Autodesk Fusion 360 part; units mm, degrees
(part 2 of 5)
equation "d84 = plt_border_width_Ref"
equation "d85 = plt_border_width_Ref"
equation "d86 = plt_border_width_Ref"
equation "d87 = plt_border_width_Ref"
equation "d88 = plt_border_width_Ref"
equation "d89 = plt_border_width_Ref"
equation "d90 = plt_border_width_Ref"
equation "d91 = plt_border_width_Ref"
equation "d92 = plt_border_width_Ref"
equation "d93 = plt_border_width_Ref"
equation "d94 = plt_border_width_Ref"
equation "d95 = plt_border_width_Ref"
equation "d96 = plt_border_width_Ref"
equation "d97 = plt_border_width_Ref"
equation "d98 = plt_border_width_Ref"
equation "d99 = plt_border_width_Ref"
equation "d100 = plt_border_width_Ref"
equation "d101 = plt_border_width_Ref"
equation "d102 = plt_border_width_Ref"
equation "d103 = -case_border_width_Ref"
equation "d104 = plt_border_width_Ref"
equation "d105 = -case_bot_max_thickness_Ref"
equation "d107 = case_border_width_Ref"
equation "d108 = case_border_width_Ref"
equation "d109 = case_border_width_Ref"
equation "d110 = case_border_width_Ref"
equation "d112 = case_border_width_Ref"
equation "d113 = case_border_width_Ref"
equation "d114 = case_border_width_Ref * 1.75"
equation "d115 = case_border_width_Ref"
equation "d116 = case_border_width_Ref"
equation "d117 = case_border_width_Ref * 1.75"
equation "d118 = case_border_width_Ref"
equation "d119 = case_border_width_Ref"
equation "d120 = case_border_width_Ref * 1.75"
equation "d121 = case_border_width_Ref"
equation "d122 = case_border_width_Ref"
equation "d123 = case_border_width_Ref * 1.75"
equation "d124 = m2scr_diameter_Ref"
equation "d125 = assemblyscr_head_diameter_Ref"
equation "d126 = assemblyscr_head_diameter_Ref"
equation "d127 = m2scr_diameter_Ref"
equation "d128 = assemblyscr_head_diameter_Ref"
equation "d129 = m2scr_diameter_Ref"
equation "d130 = assemblyscr_head_diameter_Ref"
equation "d131 = m2scr_diameter_Ref"
equation "d134 = plt_border_width_Ref + sw_size_Ref"
equation "d135 = plt_border_width_Ref + sw_size_Ref + 0.375 mm"
equation "d138 = plt_border_width_Ref + sw_size_Ref"
equation "d139 = plt_border_width_Ref + sw_size_Ref - 0.375 mm"
equation "d140 = plt_border_width_Ref + sw_size_Ref"
equation "d141 = plt_border_width_Ref + sw_size_Ref"
equation "d142 = sw_size_Ref * 3 - 0.55 mm"
equation "d146 = plt_border_width_Ref + sw_size_Ref * 3 - col_pinky_offset_Ref"
equation "d147 = sw_size_Ref * 6 + plt_border_width_Ref"
equation "d148 = plt_border_width_Ref + 13.096875 mm"
equation "d150 = sw_size_Ref * 2 + 8.334375 mm"
equation "d151 = 3.571875 mm + plt_border_width_Ref"
equation "d152 = m2scr_diameter_Ref"
equation "d153 = mtscr_head_diameter_Ref"
equation "d154 = m2scr_diameter_Ref"
equation "d155 = mtscr_head_diameter_Ref"
equation "d156 = m2scr_diameter_Ref"
equation "d157 = mtscr_head_diameter_Ref"
equation "d158 = m2scr_diameter_Ref"
equation "d159 = mtscr_head_diameter_Ref"
equation "d160 = m2scr_diameter_Ref"
equation "d161 = mtscr_head_diameter_Ref"
equation "d162 = m2scr_diameter_Ref"
equation "d163 = mtscr_head_diameter_Ref"
equation "d165 = case_border_width_Ref + plt_border_width_Ref"
equation "d166 = case_border_width_Ref + plt_border_width_Ref"
equation "d167 = sw_size_Ref * 3"
equation "d168 = plt_border_width_Ref + case_border_width_Ref"
equation "d169 = case_border_width_Ref"
equation "d170 = alignh_diameter_Ref"
equation "d171 = case_border_width_Ref + plt_border_width_Ref"
equation "d172 = alignh_diameter_Ref"
equation "d173 = case_border_width_Ref + plt_border_width_Ref"
equation "d174 = alignh_diameter_Ref"
equation "d175 = case_border_width_Ref + plt_border_width_Ref"
equation "d177 = plt_border_width_Ref + sw_size_Ref * 3"
equation "d178 = case_border_width_Ref"
equation "d179 = plt_border_width_Ref"
equation "d180 = case_border_width_Ref + plt_border_width_Ref"
equation "d181 = case_border_width_Ref"
equation "d182 = plt_border_width_Ref"
equation "d184 = sw_size_Ref * 3 + plt_border_width_Ref"
equation "d185 = case_border_width_Ref"
equation "d186 = alignh_diameter_Ref"
equation "d187 = alignh_diameter_Ref"
equation "d188 = alignh_height_Ref"
equation "d191 = ( alignh_diameter_Ref ) * 0.5"
equation "d192 = -case_bot_max_thickness_Ref + 0.5 mm"
equation "d194 = -case_bot_max_thickness_Ref + min(1 mm; case_bot_min_thickness_Ref - mtscr_head_width_Ref)"
equation "d196 = case_border_width_Ref + plt_border_width_Ref"
equation "d197 = case_border_width_Ref + plt_border_width_Ref"
equation "d198 = bat_offset_Ref - bat_length_Ref * 0.5 - bat_wall_thickness_Ref"
equation "d199 = bat_height_Ref + bat_wall_thickness_Ref * 2"
equation "d200 = bat_length_Ref + bat_wall_thickness_Ref * 2"
equation "d201 = bat_wall_thickness_Ref"
equation "d202 = bat_wall_thickness_Ref"
equation "d203 = bat_wall_thickness_Ref"
equation "d204 = ( pcb_clearance_Ref ) - ( sw_hotswap_clearance_Ref + bat_width_Ref + bat_wall_thickness_Ref + 0.05 mm )"
equation "d206 = ( bat_height_Ref + bat_wall_thickness_Ref * 2 ) * 0.5"
equation "d207 = bat_wall_thickness_Ref * 0.5"
equation "d208 = bat_wall_thickness_Ref"
equation "d209 = bat_wall_thickness_Ref"
equation "d210 = bat_length_Ref"
equation "d212 = bat_wall_thickness_Ref"
equation "d214 = ( bat_width_Ref + bat_wall_thickness_Ref ) * 0.5"
equation "d218 = bat_wall_thickness_Ref * 0.5"
equation "d219 = bat_wall_thickness_Ref"
equation "d220 = bat_length_Ref"
equation "d221 = bat_width_Ref + bat_wall_thickness_Ref"
equation "d225 = -case_bot_angle_Ref"
equation "d229 = rf_voffset_Ref"
equation "d230 = rf_hoffset_Ref"
equation "d231 = rf_voffset_Ref"
equation "d232 = rf_hoffset_Ref"
equation "d233 = rf_voffset_Ref"
equation "d234 = rf_hoffset_Ref"
equation "d235 = rf_voffset_Ref"
equation "d236 = rf_hoffset_Ref"
equation "d237 = rf_diameter_Ref"
equation "d238 = rf_diameter_Ref"
equation "d239 = rf_diameter_Ref"
equation "d240 = rf_diameter_Ref"
equation "d243 = -rf_width_Ref"
equation "d246 = case_side_fillet_Ref"
equation "case_side_fillet_Ref = 2.5 mm"
equation "case_top_fillet_Ref = 0.5 mm"
equation "case_top_inner_border_side_fillet_Ref = 1.5 mm"
equation "case_top_inner_border_top_fillet_Ref = 1 mm"
equation "usbc_contour_height_Ref = 4.5 mm"
equation "usbc_contour_length_Ref = 12 mm"
equation "assemblyscr_head_diameter_Ref = 4.15 mm"
equation "assemblyscr_head_width_Ref = 0.85 mm"
equation "rf_diameter_Ref = 10 mm"
equation "rf_width_Ref = 0.5 mm"
equation "rf_voffset_Ref = case_border_width_Ref + 10 mm"
equation "rf_hoffset_Ref = case_border_width_Ref + 15 mm"

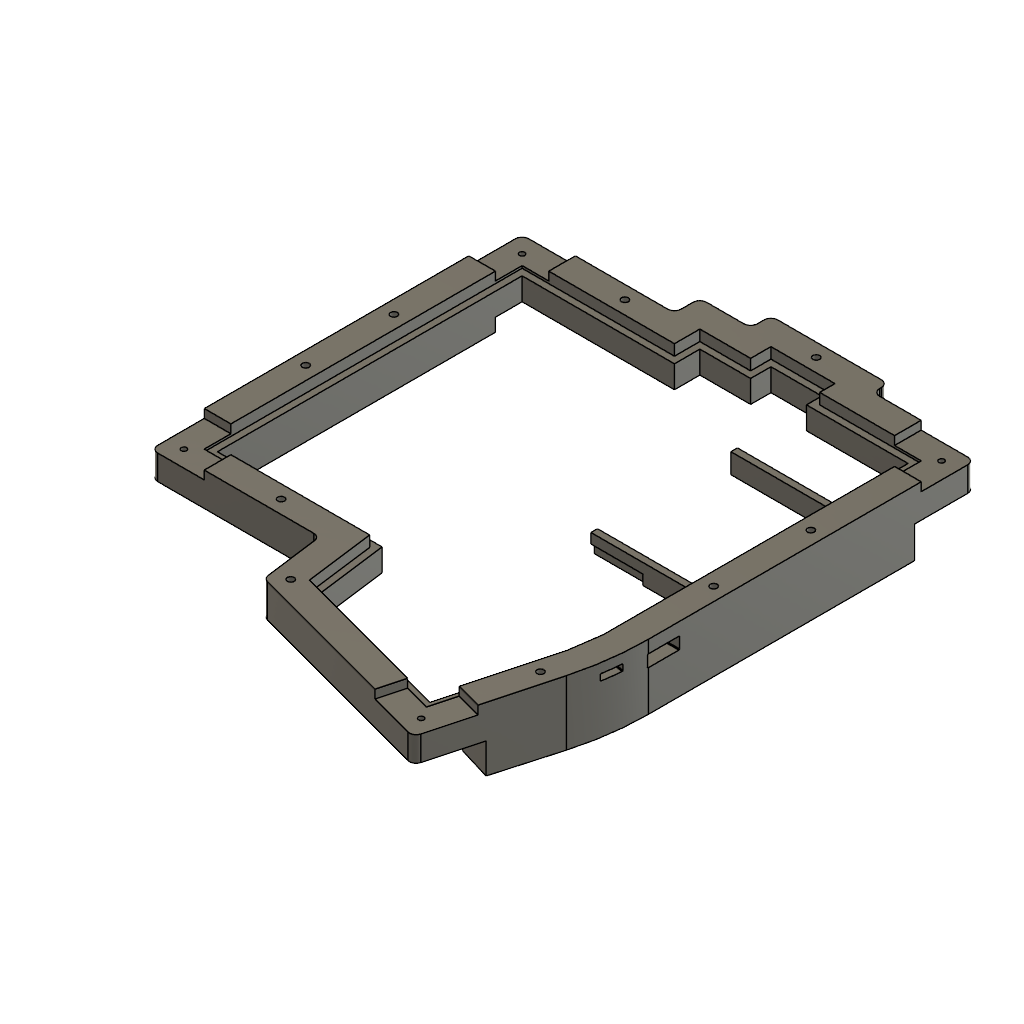
design "Case Wall (Castor)" references "_Globals"
part number: 2026-10-18-13-23-20-867
Autodesk Fusion 360 part; units mm, degrees
derive "ExternalDerived1"
sketch "Sketch1" plane through (0, 0, 0) normal (0, 1, 0) x (1, 0, 0)
  line L0 (-9.525, 57.15) -> (-66.675, 57.15) construction
  line L1 (-66.675, 57.15) -> (-66.675, -57.15) construction
  line L2 (-66.675, -57.15) -> (-9.525, -57.15) construction
  line L3 (66.675, -45.72) -> (66.675, 57.15) construction
  line L4 (66.675, 57.15) -> (-66.675, -57.15) construction
  line L5 (-66.675, 57.15) -> (66.675, -57.15) construction
  line L6 (-66.675, 57.15) -> (-9.525, 57.15) construction
  line L7 (-9.525, 57.15) -> (-9.525, 66.675) construction
  line L8 (-9.525, 66.675) -> (9.525, 66.675) construction
  line L9 (9.525, 66.675) -> (9.525, 74.295) construction
  line L10 (9.525, 74.295) -> (28.575, 74.295) construction
  line L11 (28.575, 74.295) -> (28.575, 68.58) construction
  line L12 (28.575, 68.58) -> (66.675, 68.58) construction
  line L13 (66.675, 68.58) -> (66.675, 57.15) construction
  line L14 (-66.675, -57.15) -> (-9.525, -57.15) construction
  line L15 (-9.525, -57.15) -> (-9.525, -47.625) construction
  line L16 (-9.525, -47.625) -> (9.525, -47.625) construction
  line L17 (9.525, -47.625) -> (9.525, -45.72) construction
  line L18 (9.525, -45.72) -> (66.675, -45.72) construction
  line L19 (9.525, -47.625) -> (9.525, -47.73) construction
  line L20 (9.525, -47.73) -> (9.59, -47.73) construction
  line L21 (9.59, -47.73) -> (9.7259, -47.2229) construction
  line L22 (9.7259, -47.2229) -> (9.2188, -47.087) construction
  line L23 (9.2188, -47.087) -> (27.6197, -52.0175) construction
  line L24 (27.6197, -52.0175) -> (22.6892, -70.4184) construction
  line L25 (22.6892, -70.4184) -> (4.2883, -65.4879) construction
  line L26 (4.2883, -65.4879) -> (9.2188, -47.087) construction
  line L27 (27.6197, -52.0175) -> (64.4214, -61.8785) construction
  line L28 (64.4214, -61.8785) -> (54.5604, -98.6803) construction
  line L29 (54.5604, -98.6803) -> (-0.6422, -83.8888) construction
  line L30 (-0.6422, -83.8888) -> (4.2883, -65.4879) construction
  line L31 (-66.675, -57.15) -> (-69.15, -57.15) construction
  line L32 (-69.15, -57.15) -> (-69.15, -59.625) construction
  line L33 (-9.525, -57.15) -> (-7.05, -57.15) construction
  line L34 (-7.05, -57.15) -> (-7.05, -59.625) construction
  line L35 (-0.6422, -83.8888) -> (-3.0329, -83.2482) construction
  line L36 (-3.0329, -83.2482) -> (-3.6735, -85.6389) construction
  line L37 (54.5604, -98.6803) -> (56.9511, -99.3209) construction
  line L38 (56.9511, -99.3209) -> (56.3105, -101.7115) construction
  line L39 (64.4214, -61.8785) -> (65.062, -59.4879) construction
  line L40 (65.062, -59.4879) -> (67.4527, -60.1284) construction
  line L41 (66.675, -45.72) -> (66.675, -48.195) construction
  line L42 (66.675, -48.195) -> (69.15, -48.195) construction
  line L43 (66.675, 68.58) -> (66.675, 71.055) construction
  line L44 (66.675, 71.055) -> (69.15, 71.055) construction
  line L45 (28.575, 68.58) -> (31.05, 68.58) construction
  line L46 (31.05, 68.58) -> (31.05, 71.055) construction
  line L47 (28.575, 74.295) -> (28.575, 76.77) construction
  line L48 (28.575, 76.77) -> (31.05, 76.77) construction
  line L49 (9.525, 74.295) -> (9.525, 76.77) construction
  line L50 (9.525, 76.77) -> (7.05, 76.77) construction
  line L51 (9.525, 66.675) -> (7.05, 66.675) construction
  line L52 (7.05, 66.675) -> (7.05, 69.15) construction
  line L53 (-9.525, 66.675) -> (-12, 66.675) construction
  line L54 (-12, 66.675) -> (-12, 69.15) construction
  line L55 (-9.525, 57.15) -> (-12, 57.15) construction
  line L56 (-12, 57.15) -> (-12, 59.625) construction
  line L57 (-66.675, 57.15) -> (-69.15, 57.15) construction
  line L58 (-69.15, 57.15) -> (-69.15, 59.625) construction
  line L59 (-69.15, -59.625) -> (-69.15, 59.625)
  line L60 (-69.15, 59.625) -> (-12, 59.625)
  line L61 (-12, 69.15) -> (-12, 59.625)
  line L62 (-12, 69.15) -> (7.05, 69.15)
  line L63 (7.05, 69.15) -> (7.05, 76.77)
  line L64 (7.05, 76.77) -> (31.05, 76.77)
  line L65 (31.05, 76.77) -> (31.05, 71.055)
  line L66 (31.05, 71.055) -> (69.15, 71.055)
  line L67 (69.15, 71.055) -> (69.15, -48.195)
  line L68 (69.15, -48.195) -> (67.4527, -60.1284)
  line L69 (67.4527, -60.1284) -> (56.3105, -101.7115)
  line L70 (56.3105, -101.7115) -> (-3.6735, -85.6389)
  line L71 (-3.6735, -85.6389) -> (-7.05, -59.625)
  line L72 (-7.05, -59.625) -> (-69.15, -59.625)
  line L73 (-22, 79.15) -> (-22, 69.625)
  line L74 (-79.15, 69.625) -> (-22, 69.625)
  line L75 (-79.15, -69.625) -> (-79.15, 69.625)
  line L76 (-15.8359, -69.625) -> (-79.15, -69.625)
  line L77 (-12.7285, -93.5653) -> (-15.8359, -69.625)
  line L78 (63.3816, -113.959) -> (-12.7285, -93.5653)
  line L79 (77.2681, -62.1339) -> (63.3816, -113.959)
  line L80 (79.15, -48.9026) -> (77.2681, -62.1339)
  line L81 (79.15, 81.055) -> (79.15, -48.9026)
  line L82 (41.05, 81.055) -> (79.15, 81.055)
  line L83 (41.05, 86.77) -> (41.05, 81.055)
  line L84 (-2.95, 86.77) -> (41.05, 86.77)
  line L85 (-2.95, 79.15) -> (-2.95, 86.77)
  line L86 (-22, 79.15) -> (-2.95, 79.15)
  dimension "d44" = 133.35
  dimension "d45" = 114.3
  dimension "d46" = 57.15
  dimension "d47" = 9.525
  dimension "d48" = 19.05
  dimension "d49" = 7.62
  dimension "d50" = 19.05
  dimension "d51" = 5.715
  dimension "d52" = 38.1
  dimension "d53" = 57.15
  dimension "d54" = 9.525
  dimension "d55" = 19.05
  dimension "d56" = 1.905
  dimension "d57" = 102.87
  dimension "d58" = 0.105
  dimension "d59" = 0.065
  dimension "d60" = 0.525
  dimension "d61" = 0.525
  dimension "d62" = 19.05
  dimension "d63" = 19.05
  dimension "d64" = 38.1
  dimension "d65" = 38.1
  dimension "d66" = 57.15
  dimension "d67" = 2.475
  dimension "d68" = 2.475
  dimension "d69" = 2.475
  dimension "d70" = 2.475
  dimension "d71" = 2.475
  dimension "d72" = 2.475
  dimension "d73" = 2.475
  dimension "d74" = 2.475
  dimension "d75" = 2.475
  dimension "d76" = 2.475
  dimension "d77" = 2.475
  dimension "d78" = 2.475
  dimension "d79" = 2.475
  dimension "d80" = 2.475
  dimension "d81" = 2.475
  dimension "d82" = 2.475
  dimension "d83" = 2.475
  dimension "d84" = 2.475
  dimension "d85" = 2.475
  dimension "d86" = 2.475
  dimension "d87" = 2.475
  dimension "d88" = 2.475
  dimension "d89" = 2.475
  dimension "d90" = 2.475
  dimension "d91" = 2.475
  dimension "d92" = 2.475
  dimension "d93" = 2.475
  dimension "d94" = 2.475
  constraint horizontal L0
  constraint perpendicular L0 L1
  constraint parallel L0 L2
  constraint parallel L1 L3
  constraint coincident L4 origin
  constraint coincident L5 origin
  constraint perpendicular L1 L6
  constraint perpendicular L0 L7
  constraint perpendicular L7 L8
  constraint perpendicular L0 L9
  constraint perpendicular L9 L10
  constraint perpendicular L0 L11
  constraint perpendicular L11 L12
  constraint perpendicular L1 L14
  constraint perpendicular L2 L15
  constraint perpendicular L15 L16
  constraint perpendicular L2 L17
  constraint perpendicular L3 L18
  constraint collinear L3 L13
  constraint vertical L19
  constraint perpendicular L19 L20
  constraint perpendicular L21 L22
  constraint parallel L24 L26
  constraint parallel L23 L25
  constraint perpendicular L24 L25
  constraint collinear L22 L23
  constraint perpendicular L24 L27
  constraint perpendicular L27 L28
  constraint perpendicular L28 L29
  constraint perpendicular L1 L31
  constraint perpendicular L14 L32
  constraint perpendicular L15 L33
  constraint perpendicular L2 L34
  constraint perpendicular L30 L35
  constraint perpendicular L29 L36
  constraint perpendicular L28 L37
  constraint perpendicular L29 L38
  constraint perpendicular L27 L39
  constraint perpendicular L39 L40
  constraint perpendicular L18 L41
  constraint perpendicular L3 L42
  constraint perpendicular L12 L43
  constraint perpendicular L13 L44
  constraint perpendicular L11 L45
  constraint perpendicular L12 L46
  constraint perpendicular L10 L47
  constraint perpendicular L47 L48
  constraint perpendicular L10 L49
  constraint perpendicular L9 L50
  constraint perpendicular L9 L51
  constraint perpendicular L51 L52
  constraint perpendicular L7 L53
  constraint perpendicular L8 L54
  constraint perpendicular L7 L55
  constraint perpendicular L6 L56
  constraint perpendicular L1 L57
  constraint perpendicular L57 L58
  measures "d44" distance of L1.end L5.end
  measures "d45" distance of L0.end L1.end
  measures "d46" distance of L0.end L0.start
  measures "d47" distance of L0.start L7.end
  measures "d48" distance of L7.end L8.end
  measures "d49" distance of L8.end L9.end
  measures "d50" distance of L9.end L10.end
  measures "d51" distance of L10.end L11.end
  measures "d52" distance of L11.end L12.end
  measures "d53" distance of L1.end L2.end
  measures "d54" distance of L2.end L15.end
  measures "d55" distance of L15.end L16.end
  measures "d56" distance of L16.end L17.end
  measures "d57" distance of L3.end L3.start
  measures "d58" distance of L16.end L19.end
  measures "d59" distance of L19.end L20.end
  measures "d60" distance of L20.end L21.end
  measures "d61" distance of L21.end L22.end
  measures "d62" distance of L22.end L23.end
  measures "d63" distance of L22.end L25.end
  measures "d64" distance of L23.end L27.end
  measures "d65" distance of L27.end L28.end
  measures "d66" distance of L28.end L29.end
  measures "d67" distance of L1.end L31.end
  measures "d68" distance of L31.end L32.end
  measures "d69" distance of L2.end L33.end
  measures "d70" distance of L33.end L34.end
  measures "d71" distance of L29.end L35.end
  measures "d72" distance of L35.end L36.end
  measures "d73" distance of L28.end L37.end
  measures "d74" distance of L37.end L38.end
  measures "d75" distance of L27.end L39.end
  measures "d76" distance of L39.end L40.end
  measures "d77" distance of L3.start L41.end
  measures "d78" distance of L41.end L42.end
  measures "d79" distance of L12.end L43.end
  measures "d80" distance of L43.end L44.end
  measures "d81" distance of L11.end L45.end
  measures "d82" distance of L45.end L46.end
  measures "d83" distance of L10.end L47.end
  measures "d84" distance of L47.end L48.end
  measures "d85" distance of L9.end L49.end
  measures "d86" distance of L49.end L50.end
  measures "d87" distance of L8.end L51.end
  measures "d88" distance of L51.end L52.end
  measures "d89" distance of L7.end L53.end
  measures "d90" distance of L53.end L54.end
  measures "d91" distance of L0.start L55.end
  measures "d92" distance of L55.end L56.end
  measures "d93" distance of L0.end L57.end
  measures "d94" distance of L57.end L58.end
extrude "Extrude1" add sketch "Sketch1" along normal blind 24.3975
sketch "Sketch2" plane through (0, 24.3975, 0) normal (0, 1, 0) x (-1, 0, 0)
  line L0 (12, -59.625) -> (12, -69.15)
  line L1 (12, -69.15) -> (-7.05, -69.15)
  line L2 (-7.05, -69.15) -> (-7.05, -76.77)
  line L3 (-7.05, -76.77) -> (-31.05, -76.77)
  line L4 (-31.05, -76.77) -> (-31.05, -71.055)
  line L5 (-31.05, -71.055) -> (-69.15, -71.055)
  line L6 (-69.15, -71.055) -> (-69.15, 48.195)
  line L7 (-69.15, 48.195) -> (-67.4527, 60.1284)
  line L8 (-67.4527, 60.1284) -> (-56.3105, 101.7115)
  line L9 (-56.3105, 101.7115) -> (3.6735, 85.6389)
  line L10 (3.6735, 85.6389) -> (7.05, 59.625)
  line L11 (7.05, 59.625) -> (69.15, 59.625)
  line L12 (69.15, 59.625) -> (69.15, -59.625)
  line L13 (69.15, -59.625) -> (12, -59.625)
  line L14 (22, -79.15) -> (22, -69.625)
  line L15 (22, -69.625) -> (79.15, -69.625)
  line L16 (79.15, -69.625) -> (79.15, 69.625)
  line L17 (79.15, 69.625) -> (15.8359, 69.625)
  line L18 (15.8359, 69.625) -> (12.7285, 93.5653)
  line L19 (12.7285, 93.5653) -> (-63.3816, 113.959)
  line L20 (-63.3816, 113.959) -> (-77.2681, 62.1339)
  line L21 (-77.2681, 62.1339) -> (-79.15, 48.9026)
  line L22 (-79.15, 48.9026) -> (-79.15, -81.055)
  line L23 (-79.15, -81.055) -> (-41.05, -81.055)
  line L24 (-41.05, -81.055) -> (-41.05, -86.77)
  line L25 (-41.05, -86.77) -> (2.95, -86.77)
  line L26 (2.95, -86.77) -> (2.95, -79.15)
  line L27 (2.95, -79.15) -> (22, -79.15)
  line L28 (69.15, -59.625) -> (59.15, -59.625)
  line L29 (59.15, -59.625) -> (59.15, -69.625)
  line L30 (69.15, -59.625) -> (69.15, -49.625)
  line L31 (69.15, -49.625) -> (79.15, -49.625)
  line L32 (-69.15, -71.055) -> (-59.15, -71.055)
  line L33 (-59.15, -71.055) -> (-59.15, -81.055)
  line L34 (-69.15, -71.055) -> (-69.15, -61.055)
  line L35 (-69.15, -61.055) -> (-79.15, -61.055)
  line L36 (69.15, 59.625) -> (59.15, 59.625)
  line L37 (59.15, 59.625) -> (59.15, 69.625)
  line L38 (69.15, 59.625) -> (69.15, 49.625)
  line L39 (69.15, 49.625) -> (79.15, 49.625)
  line L40 (-56.3105, 101.7115) -> (-46.6513, 99.1233)
  line L41 (-46.6513, 99.1233) -> (-44.0631, 108.7826)
  line L42 (-56.3105, 101.7115) -> (-58.8987, 92.0523)
  line L43 (-58.8987, 92.0523) -> (-68.558, 94.6405)
  line L44 (-56.3105, 101.7115) -> (-63.3816, 113.959) construction
  line L45 (69.15, 59.625) -> (79.15, 69.625) construction
  line L46 (69.15, -59.625) -> (79.15, -69.625) construction
  line L47 (-69.15, -71.055) -> (-79.15, -81.055) construction
  circle A0 centre (79.15, -69.625) radius 8.75 construction
  circle A1 centre (-79.15, -81.055) radius 8.75 construction
  circle A2 centre (-63.3816, 113.959) radius 8.75 construction
  circle A3 centre (79.15, 69.625) radius 8.75 construction
  circle A4 centre (72.9628, 63.4378) radius 1.025
  circle A5 centre (-59.0066, 106.3813) radius 1.025
  circle A6 centre (-72.9628, -74.8678) radius 1.025
  circle A7 centre (72.9628, -63.4378) radius 1.025
  line L48 (-19.05, -86.77) -> (-19.05, -76.77) construction
  line L49 (59.15, -59.625) -> (12, -59.625) construction
  line L50 (35.575, -59.625) -> (35.575, -69.625) construction
  circle A8 centre (35.575, -64.625) radius 1.275
  circle A9 centre (-19.05, -81.77) radius 1.275
  line L51 (15.8359, 69.625) -> (7.05, 59.625) construction
  line L52 (3.6735, 85.6389) -> (12.7285, 93.5653) construction
  line L53 (59.15, 64.625) -> (11.443, 64.625) construction
  circle A10 centre (35.2965, 64.625) radius 1.275
  line L54 (-26.3185, 93.6752) -> (-23.7303, 103.3345) construction
  line L55 (14.2822, 81.5952) -> (5.3617, 72.6319) construction
  line L56 (9.822, 77.1136) -> (-25.0244, 98.5048) construction
  line L57 (-7.6012, 87.8092) -> (12.7285, 93.5653) construction
  line L58 (2.5637, 90.6873) -> (8.201, 89.6021) construction
  line L59 (2.5637, 90.6873) -> (6.6059, 88.2058) construction
  line L60 (6.6059, 88.2058) -> (8.201, 89.6021) construction
  circle A11 centre (7.4035, 88.904) radius 1.275
  line L61 (74.15, -49.625) -> (74.15, 49.625) construction
  line L62 (74.15, -49.625) -> (143.9366, 68.7503) construction
  circle A12 centre (74.15, -49.625) radius 30 construction
  circle A13 centre (89.3856, -23.7817) radius 30 construction
  circle A14 centre (104.6212, 2.0616) radius 30 construction
  line L63 (119.8568, 27.9049) -> (74.15, 49.625) construction
  circle A15 centre (119.8568, 27.9049) radius 30 construction
  line L64 (104.6212, 2.0616) -> (92.7606, 40.7812) construction
  circle A16 centre (74.15, -49.625) radius 40.4954 construction
  circle A17 centre (89.3856, -23.7817) radius 40.4954 construction
  line L65 (89.3856, -23.7817) -> (129.6396, -28.1962) construction
  line L66 (74.15, -49.625) -> (114.404, -54.0395) construction
  line L67 (77.525, 14.9378) -> (104.6212, 2.0616) construction
  line L68 (77.525, 14.9378) -> (34.0227, 35.6103) construction
  line L69 (89.3856, -23.7817) -> (62.2894, -10.9055) construction
  circle A18 centre (74.15, 16.5417) radius 1.275
  circle A19 centre (74.15, -16.5417) radius 1.275
  line L70 (-69.15, 48.195) -> (-79.15, 48.195) construction
  line L71 (-74.15, 48.195) -> (-74.15, -61.055) construction
  line L72 (-74.15, -61.055) -> (-143.6538, 60.5776) construction
  circle A20 centre (-74.15, -61.055) radius 30 construction
  circle A21 centre (-89.0341, -35.0077) radius 30 construction
  circle A22 centre (-103.9182, -8.9603) radius 30 construction
  line L73 (-118.8022, 17.087) -> (-74.15, 48.195) construction
  circle A23 centre (-118.8022, 17.087) radius 30 construction
  line L74 (-103.9182, -8.9603) -> (-94.1868, 34.2359) construction
  circle A24 centre (-74.15, -61.055) radius 44.2788 construction
  circle A25 centre (-89.0341, -35.0077) radius 44.2788 construction
  line L75 (-74.15, -61.055) -> (-114.463, -79.371) construction
  line L76 (-89.0341, -35.0077) -> (-129.347, -53.3236) construction
  line L77 (-89.0341, -35.0077) -> (-64.4187, -17.8588) construction
  line L78 (-103.9182, -8.9603) -> (-79.3028, 8.1885) construction
  line L79 (-79.3028, 8.1885) -> (-64.4187, 18.5579) construction
  circle A26 centre (-74.15, 11.7783) radius 1.275
  circle A27 centre (-74.15, -24.6383) radius 1.275
  line L80 (-67.4527, 60.1284) -> (-77.1119, 62.7166) construction
  line L81 (-63.7283, 93.3464) -> (-72.2823, 61.4225) construction
  line L82 (-72.2823, 61.4225) -> (-84.2833, 106.1662) construction
  circle A28 centre (-72.2823, 61.4225) radius 10 construction
  circle A29 centre (-74.8729, 71.0811) radius 10 construction
  circle A30 centre (-77.4635, 80.7398) radius 10 construction
  line L83 (-80.0541, 90.3984) -> (-63.7283, 93.3464) construction
  circle A31 centre (-80.0541, 90.3984) radius 10 construction
  line L84 (-77.4635, 80.7398) -> (-70.2132, 92.1754) construction
  circle A32 centre (-72.2823, 61.4225) radius 13.5403 construction
  line L85 (-72.2823, 61.4225) -> (-58.8852, 63.3864) construction
  line L86 (-65.032, 72.8581) -> (-74.8729, 71.0811) construction
  circle A33 centre (-69.431, 72.0638) radius 1.275
  dimension "d105" = 10
  dimension "d106" = 10
  dimension "d107" = 10
  dimension "d108" = 10
  dimension "d109" = 10
  dimension "d110" = 10
  dimension "d111" = 10
  dimension "d112" = 10
  dimension "d113" = 17.5
  dimension "d114" = 17.5
  dimension "d115" = 17.5
  dimension "d116" = 17.5
  dimension "d117" = 2.05
  dimension "d118" = 2.05
  dimension "d119" = 2.05
  dimension "d120" = 2.05
  dimension "d122" = 2.55
  dimension "d123" = 2.55
  dimension "d124" = 2.55
  dimension "d125" = 2.55
  dimension "d126" = 60
  dimension "d127" = 60
  dimension "d128" = 60
  dimension "d129" = 2.55
  dimension "d130" = 2.55
  dimension "d131" = 60
  dimension "d132" = 60
  dimension "d133" = 60
  dimension "d134" = 2.55
  dimension "d135" = 2.55
  dimension "d195" = 20
  dimension "d196" = 2.55
  constraint coincident L12.end L13.start
  constraint perpendicular L12 L28
  constraint coincident L15 L29.end
  constraint perpendicular L15 L29
  constraint perpendicular L13 L30
  constraint coincident L16 L31.end
  constraint perpendicular L16 L31
  constraint coincident L5.end L6.start
  constraint perpendicular L6 L32
  constraint coincident L23 L33.end
  constraint perpendicular L23 L33
  constraint perpendicular L5 L34
  constraint coincident L22 L35.end
  constraint perpendicular L22 L35
  constraint coincident L11.end L12.start
  constraint perpendicular L12 L36
  constraint coincident L17 L37.end
  constraint perpendicular L17 L37
  constraint perpendicular L11 L38
  constraint coincident L16 L39.end
  constraint perpendicular L16 L39
  constraint coincident L8.end L9.start
  constraint coincident L9 L40.end
  constraint coincident L19 L41.end
  constraint perpendicular L19 L41
  constraint perpendicular L9 L42
  constraint coincident L20 L43.end
  constraint perpendicular L20 L43
  constraint coincident L19.end L20.start
  constraint coincident L16.end L17.start
  constraint coincident L15.end L16.start
  constraint coincident L22.end L23.start
  constraint coincident A3 A4.centre
  constraint coincident L45 A4.centre
  constraint coincident A2 A5.centre
  constraint coincident L44 A5.centre
  constraint coincident A1 A6.centre
  constraint coincident L47 A6.centre
  constraint coincident A0 A7.centre
  constraint coincident L46 A7.centre
  constraint midpoint L25 L48.start
  constraint midpoint L3 L48.end
  constraint coincident L0.start L13.end
  constraint midpoint L49 L50.start
  constraint coincident L15 L50.end
  constraint perpendicular L15 L50
  constraint midpoint L50 A8.centre
  constraint midpoint L48 A9.centre
  constraint coincident L17.end L18.start
  constraint coincident L10.end L11.start
  constraint coincident L9.end L10.start
  constraint coincident L18.end L19.start
  constraint midpoint L37 L53.start
  constraint midpoint L51 L53.end
  constraint midpoint L53 A10.centre
  constraint midpoint L9 L54.start
  constraint coincident L19 L54.end
  constraint perpendicular L19 L54
  constraint midpoint L18 L55.start
  constraint midpoint L10 L55.end
  constraint midpoint L55 L56.start
  constraint midpoint L54 L56.end
  constraint midpoint L56 L57.start
  constraint midpoint L57 L58.start
  constraint midpoint L52 L58.end
  constraint coincident L52 L59.end
  constraint parallel L56 L59
  constraint midpoint L60 A11.centre
  constraint midpoint L31 L61.start
  constraint midpoint L39 L61.end
  constraint coincident L61.start L62.start
  constraint coincident A12 A13.centre
  constraint coincident L62 A13.centre
  constraint coincident A13 A14.centre
  constraint coincident L62 A14.centre
  constraint coincident A14 L63.start
  constraint coincident L62 L63.start
  constraint coincident L63.start A15.centre
  constraint coincident A14.centre A15
  constraint coincident A14.centre L64.start
  constraint coincident A15 L64.end
  constraint coincident L63 L64.end
  constraint concentric A13 A17
  constraint coincident A13.centre A17.centre
  constraint coincident A17 L65.end
  constraint coincident A16 L66.end
  constraint parallel L65 L66
  constraint equal L64 L66
  constraint equal L64 L65
  constraint coincident A14 L67.start
  constraint coincident A17 L67.start
  constraint perpendicular A14 L68
  constraint coincident A16 L69.end
  constraint coincident A13 L69.end
  constraint coincident L68 A18.centre
  constraint coincident L61 A18.centre
  constraint coincident L69 A19.centre
  constraint coincident L61 A19.centre
  constraint coincident L6.end L7.start
  constraint coincident L22 L70.end
  constraint perpendicular L22 L70
  constraint midpoint L70 L71.start
  constraint midpoint L35 L71.end
  constraint coincident L71.end L72.start
  constraint coincident A20 A21.centre
  constraint coincident L72 A21.centre
  constraint coincident A21 A22.centre
  constraint coincident L72 A22.centre
  constraint coincident A22 L73.start
  constraint coincident L72 L73.start
  constraint coincident L73.start A23.centre
  constraint coincident A22.centre A23
  constraint coincident A22.centre L74.start
  constraint coincident A23 L74.end
  constraint coincident L73 L74.end
  constraint concentric A21 A25
  constraint coincident A24 L75.end
  constraint coincident A21.centre A25.centre
  constraint coincident A25 L76.end
  constraint parallel L75 L76
  constraint equal L74 L76
  constraint equal L74 L75
  constraint coincident A24 L77.end
  constraint coincident A21 L77.end
  constraint coincident A22 L78.end
  constraint coincident A25 L78.end
  constraint parallel L78 L79
  constraint coincident L79 A26.centre
  constraint coincident L71 A26.centre
  constraint coincident L77 A27.centre
  constraint coincident L71 A27.centre
  constraint coincident L7.end L8.start
  constraint coincident L20 L80.end
  constraint perpendicular L20 L80
  constraint midpoint L43 L81.start
  constraint midpoint L80 L81.end
  constraint coincident L81.end L82.start
  constraint coincident A28 A29.centre
  constraint coincident L82 A29.centre
  constraint coincident L81.end A29
  constraint coincident A29 A30.centre
  constraint coincident L82 A30.centre
  constraint coincident A29.centre A30
  constraint coincident L82 L83.start
  constraint coincident A30 L83.start
  constraint coincident L83.start A31.centre
  constraint coincident A30.centre A31
  constraint coincident A30.centre L84.start
  constraint coincident A31 L84.end
  constraint coincident L83 L84.end
  constraint concentric A28 A32
  constraint coincident A32 L85.end
  constraint equal L84 L85
  constraint coincident A32 L86.start
  constraint coincident A29 L86.start
  constraint coincident A29.centre L86.end
  constraint coincident L86 A33.centre
  constraint coincident L81 A33.centre
  measures "d105" distance of L12.end L28.end
  measures "d106" distance of L12.end L30.end
  measures "d107" distance of L5.end L32.end
  measures "d108" distance of L5.end L34.end
  measures "d109" distance of L11.end L36.end
  measures "d110" distance of L11.end L38.end
  measures "d111" distance of L8.end L40.end
  measures "d112" distance of L8.end L42.end
  measures "d113" diameter of A0
  measures "d114" diameter of A1
  measures "d115" diameter of A2
  measures "d116" diameter of A3
  measures "d117" diameter of A4
  measures "d118" diameter of A5
  measures "d119" diameter of A6
  measures "d120" diameter of A7
  measures "d122" diameter of A8
  measures "d123" diameter of A9
  measures "d124" diameter of A10
  measures "d125" diameter of A11
  measures "d126" diameter of A12
  measures "d127" diameter of A13
  measures "d128" diameter of A14
  measures "d129" diameter of A18
  measures "d130" diameter of A19
  measures "d131" diameter of A20
  measures "d132" diameter of A21
  measures "d133" diameter of A22
  measures "d134" diameter of A26
  measures "d135" diameter of A27
  measures "d195" diameter of A28
  measures "d196" diameter of A33
extrude "Extrude2" cut sketch "Sketch2" against normal blind 4.95 contours A8 | A9 | A10 | A11 | A18 | A19 | A26 | A27 | A33
fillet "Fillet1" radius 1.275 9 edges at (-34.1078, 19.4475, 65.0861) (-6.2147, 19.4475, 89.365) (75.3387, 19.4475, 12.2394) (75.3387, 19.4475, -24.1773) (20.2387, 19.4475, -81.3089) (-34.3863, 19.4475, -64.1639) (-72.9613, 19.4475, 17.0027) (-72.9613, 19.4475, -16.0806) (70.6197, 19.4475, 72.5249)
extrude "Extrude3" cut sketch "Sketch2" against normal through all contours A4 | A5 | A6 | A7
sketch "Sketch3" plane through (0, 24.3975, 0) normal (0, 1, 0) x (-1, 0, 0)
  circle A0 centre (35.575, -64.625) radius 1.275
  circle A1 centre (7.4035, 88.904) radius 1.275
  circle A2 centre (-19.05, -81.77) radius 1.275
  circle A3 centre (74.15, -16.5417) radius 1.275
  circle A4 centre (-74.15, 11.7783) radius 1.275
  circle A5 centre (35.2965, 64.625) radius 1.275
  circle A6 centre (-74.15, -24.6383) radius 1.275
  circle A7 centre (74.15, 16.5417) radius 1.275
  line L0 (12, -59.625) -> (12, -69.15)
  line L1 (12, -69.15) -> (-7.05, -69.15)
  line L2 (-7.05, -69.15) -> (-7.05, -76.77)
  line L3 (-7.05, -76.77) -> (-31.05, -76.77)
  line L4 (-31.05, -76.77) -> (-31.05, -71.055)
  line L5 (-31.05, -71.055) -> (-69.15, -71.055)
  line L6 (-69.15, -71.055) -> (-69.15, 48.195)
  line L7 (-69.15, 48.195) -> (-67.4527, 60.1284)
  line L8 (-67.4527, 60.1284) -> (-56.3105, 101.7115)
  line L9 (-56.3105, 101.7115) -> (3.6735, 85.6389)
  line L10 (3.6735, 85.6389) -> (7.05, 59.625)
  line L11 (7.05, 59.625) -> (69.15, 59.625)
  line L12 (69.15, 59.625) -> (69.15, -59.625)
  line L13 (69.15, -59.625) -> (12, -59.625)
  line L14 (22, -79.15) -> (22, -69.625)
  line L15 (22, -69.625) -> (79.15, -69.625)
  line L16 (79.15, -69.625) -> (79.15, 69.625)
  line L17 (79.15, 69.625) -> (15.8359, 69.625)
  line L18 (15.8359, 69.625) -> (12.7285, 93.5653)
  line L19 (12.7285, 93.5653) -> (-63.3816, 113.959)
  line L20 (-63.3816, 113.959) -> (-77.2681, 62.1339)
  line L21 (-77.2681, 62.1339) -> (-79.15, 48.9026)
  line L22 (-79.15, 48.9026) -> (-79.15, -81.055)
  line L23 (-79.15, -81.055) -> (-41.05, -81.055)
  line L24 (-41.05, -81.055) -> (-41.05, -86.77)
  line L25 (-41.05, -86.77) -> (2.95, -86.77)
  line L26 (2.95, -86.77) -> (2.95, -79.15)
  line L27 (2.95, -79.15) -> (22, -79.15)
  circle A8 centre (72.9628, -63.4378) radius 1.025
  circle A9 centre (72.9628, 63.4378) radius 1.025
  circle A10 centre (-72.9628, -74.8678) radius 1.025
  circle A11 centre (-59.0066, 106.3813) radius 1.025
  line L28 (9.525, -57.15) -> (9.525, -66.675)
  line L29 (9.525, -66.675) -> (-9.525, -66.675)
  line L30 (-9.525, -66.675) -> (-9.525, -74.295)
  line L31 (-9.525, -74.295) -> (-28.575, -74.295)
  line L32 (-28.575, -74.295) -> (-28.575, -68.58)
  line L33 (-28.575, -68.58) -> (-66.675, -68.58)
  line L34 (-66.675, -68.58) -> (-66.675, 48.0199)
  line L35 (-66.675, 48.0199) -> (-65.0234, 59.6321)
  line L36 (-65.0234, 59.6321) -> (-54.5604, 98.6803)
  line L37 (-54.5604, 98.6803) -> (1.4324, 83.6771)
  line L38 (1.4324, 83.6771) -> (4.8755, 57.15)
  line L39 (4.8755, 57.15) -> (66.675, 57.15)
  line L40 (66.675, 57.15) -> (66.675, -57.15)
  line L41 (66.675, -57.15) -> (9.525, -57.15)
  circle A12 centre (-69.431, 72.0638) radius 1.275
  dimension "d141" = 2.475
extrude "Extrude6" cut sketch "Sketch2" against normal blind 3.2 contours L12 L13 L15 L16 L28 L29 L30 L31 | L11 L12 L16 L17 L36 L37 L38 L39 | L5 L6 L22 L23 L32 L33 L34 L35 | L8 L9 L19 L20 L40 L41 L42 L43
extrude "Extrude4" add sketch "Sketch3" against normal blind 4.05 contours L0 L1 L2 L3 L4 L5 L6 L7 L8 L9 L10 L11 L12 L13
extrude "Extrude7" add 1 faces at (68.325, 20.3475, -30.48) along direction (0, -1, 0) blind 20.3475
extrude "Extrude8" cut sketch "Sketch3" against normal blind 4.05 contours L0 L1 L2 L3 L4 L5 L6 L7 L8 L9 L10 L11 L12 L13
sketch "Sketch4" plane through (66.675, 0, 0) normal (-1, 0, 0) x (0, 0, 1)
  line L0 (48.0199, 20.3475) -> (-68.58, 20.3475)
  line L1 (-68.58, 20.3475) -> (-68.58, 0)
  line L2 (-68.58, 0) -> (48.0199, 0)
  line L3 (48.0199, 0) -> (48.0199, 20.3475)
  line L4 (-68.58, 20.3475) -> (35.61, 20.3475) construction
  line L5 (35.61, 20.3475) -> (35.61, 16.1565) construction
  line L6 (31.44, 18.7165) -> (39.78, 18.7165) construction
  line L7 (39.78, 18.7165) -> (39.78, 16.1565) construction
  line L8 (39.78, 16.1565) -> (31.44, 16.1565) construction
  line L9 (31.44, 16.1565) -> (31.44, 18.7165) construction
  line L10 (31.44, 18.7165) -> (39.78, 16.1565) construction
  line L11 (39.78, 18.7165) -> (31.44, 16.1565) construction
  line L12 (41.61, 19.6865) -> (29.61, 19.6865)
  line L13 (29.61, 19.6865) -> (29.61, 15.1865)
  line L14 (29.61, 15.1865) -> (41.61, 15.1865)
  line L15 (41.61, 15.1865) -> (41.61, 19.6865)
  line L16 (41.61, 19.6865) -> (29.61, 15.1865) construction
  line L17 (29.61, 19.6865) -> (41.61, 15.1865) construction
  line L18 (-68.58, 20.3475) -> (-16.08, 20.3475) construction
  line L19 (-16.08, 20.3475) -> (-16.08, 18.4475) construction
  line L20 (-16.08, 18.4475) -> (-16.08, 15.9475) construction
  line L21 (8.92, 18.4475) -> (-41.08, 18.4475)
  line L22 (-41.08, 18.4475) -> (-41.08, 13.4475) construction
  line L23 (-41.08, 13.4475) -> (8.92, 13.4475)
  line L24 (8.92, 13.4475) -> (8.92, 18.4475) construction
  line L25 (8.92, 18.4475) -> (-41.08, 13.4475) construction
  line L26 (-41.08, 18.4475) -> (8.92, 13.4475) construction
  line L27 (8.92, 18.4475) -> (11.42, 18.4475)
  line L28 (11.42, 18.4475) -> (11.42, 10.9475)
  line L29 (11.42, 10.9475) -> (8.92, 10.9475)
  line L30 (8.92, 10.9475) -> (8.92, 18.4475)
  line L31 (-43.58, 10.9475) -> (-41.08, 10.9475)
  line L32 (-41.08, 10.9475) -> (-41.08, 18.4475)
  line L33 (-41.08, 18.4475) -> (-43.58, 18.4475)
  line L34 (-43.58, 18.4475) -> (-43.58, 10.9475)
  line L35 (35.61, 20.3475) -> (44.86, 20.3475) construction
  line L36 (44.86, 20.3475) -> (26.36, 20.3475)
  line L37 (26.36, 20.3475) -> (26.36, 14.4565)
  line L38 (26.36, 14.4565) -> (44.86, 14.4565)
  line L39 (44.86, 14.4565) -> (44.86, 20.3475)
  point P0 (35.61, 17.4365)
  point P1 (-16.08, 15.9475)
  point P2 (35.61, 17.4365)
  dimension "d153" = 104.19
  dimension "d155" = 4.191
  dimension "d156" = 8.34
  dimension "d157" = 2.56
  dimension "d158" = 12
  dimension "d159" = 4.5
  dimension "d164" = 52.5
  dimension "d166" = 1.9
  dimension "d167" = 2.5
  dimension "d168" = 50
  dimension "d169" = 5
  dimension "d173" = 2.5
  dimension "d174" = 7.5
  dimension "d237" = 9.25
  dimension "d238" = 18.5
  dimension "d239" = 5.891
  constraint coincident L0.end L1.start
  constraint perpendicular L1 L4
  constraint perpendicular L0 L5
  constraint horizontal L6
  constraint vertical L7
  constraint horizontal L8
  constraint vertical L9
  constraint midpoint L5.end L8
  constraint horizontal L12
  constraint perpendicular L12 L13
  constraint parallel L12 L14
  constraint parallel L13 L15
  constraint coincident L16 P2
  constraint coincident L17 P2
  constraint midpoint L11 P2
  constraint perpendicular L1 L18
  constraint perpendicular L4 L19
  constraint perpendicular L4 L20
  constraint horizontal L21
  constraint perpendicular L21 L22
  constraint parallel L21 L23
  constraint parallel L22 L24
  constraint coincident L25 P1
  constraint coincident L26 P1
  constraint coincident P1 L20.end
  constraint horizontal L27
  constraint vertical L28
  constraint horizontal L29
  constraint vertical L30
  constraint symmetric L20 L21.start L21.end
  constraint symmetric L20 L27.end L33.end
  constraint symmetric L20 L28.end L31.start
  constraint symmetric L20 L29.end L31.end
  constraint coincident P2 P0
  constraint perpendicular L5 L35
  constraint horizontal L36
  constraint vertical L37
  constraint horizontal L38
  constraint vertical L39
  measures "d153" distance of L0.end L4.end
  measures "d155" distance of L4.end L5.end
  measures "d156" distance of L6.start L6.end
  measures "d157" distance of L6.start L8.end
  measures "d158" distance of L13.end L14.end
  measures "d159" distance of L12.end L13.end
  measures "d164" distance of L0.end L18.end
  measures "d166" distance of L18.end L19.end
  measures "d167" distance of L19.end P1
  measures "d168" distance of L22.end L23.end
  measures "d169" distance of L21.end L22.end
  measures "d173" distance of L21.start L27.end
  measures "d174" distance of L21.start L29.end
  measures "d237" distance of L4.end L35.end
  measures "d238" distance of L35.end L36.end
  measures "d239" distance of L35.end L38.end
extrude "Extrude9" cut sketch "Sketch4" against normal through all contours L12 L13 L14 L15
extrude "Extrude10" add sketch "Sketch4" along normal blind 2.5 contours L21 L23 L30 L32
extrude "Extrude11" add sketch "Sketch4" along normal blind 39 contours L27 L28 L29 L30 | L31 L32 L33 L34
sketch "Sketch5" plane through (0, 0, 11.42) normal (0, 0, 1) x (1, 0, 0)
  line L0 (66.675, 10.9475) -> (66.675, 18.4475)
  line L1 (66.675, 18.4475) -> (27.675, 18.4475)
  line L2 (27.675, 18.4475) -> (27.675, 10.9475)
  line L3 (27.675, 10.9475) -> (66.675, 10.9475)
  line L4 (47.175, 10.9475) -> (47.175, 18.4475) construction
  line L5 (47.175, 14.6975) -> (27.675, 14.6975)
  line L6 (47.175, 14.6975) -> (47.175, 10.9475)
  constraint midpoint L3 L4.start
  constraint midpoint L1 L4.end
  constraint midpoint L4 L5.start
  constraint midpoint L2 L5.end
extrude "Extrude12" cut sketch "Sketch5" against normal blind 1.25 contours L2 L3 L5 L6
sketch "Sketch6" plane through (0, 0, -43.58) normal (0, 0, -1) x (-1, 0, 0)
  line L0 (-66.675, 18.4475) -> (-66.675, 10.9475)
  line L1 (-66.675, 10.9475) -> (-27.675, 10.9475)
  line L2 (-27.675, 10.9475) -> (-27.675, 18.4475)
  line L3 (-27.675, 18.4475) -> (-66.675, 18.4475)
  line L4 (-47.175, 10.9475) -> (-47.175, 18.4475) construction
  line L5 (-47.175, 14.6975) -> (-27.675, 14.6975)
  line L6 (-47.175, 14.6975) -> (-47.175, 10.9475)
  constraint midpoint L1 L4.start
  constraint midpoint L3 L4.end
  constraint midpoint L4 L5.start
  constraint midpoint L2 L5.end
extrude "Extrude13" cut sketch "Sketch6" against normal blind 1.25 contours L1 L2 L5 L6
extrude "Extrude14" cut sketch "Sketch4" against normal blind 2.475 contours L0 L36 L37 L38 L39
sketch "Sketch7" plane through (72.0475, 0, 10.2475) normal (-0.990036, 0, -0.140816) x (-0.140816, 0, 0.990036)
  line L0 (49.8816, 20.3475) -> (38.1525, 20.3475)
  line L1 (38.1525, 0) -> (49.8816, 0)
  line L2 (49.8816, 0) -> (49.8816, 20.3475)
  line L3 (38.1525, 20.3475) -> (38.1525, 18.4475) construction
  line L4 (38.1525, 18.4475) -> (38.8695, 18.4475) construction
  line L5 (38.8695, 18.4475) -> (46.4695, 18.4475)
  line L6 (46.4695, 18.4475) -> (46.4695, 20.8475)
  line L7 (46.4695, 20.8475) -> (38.8695, 20.8475)
  line L8 (38.8695, 20.8475) -> (38.8695, 18.4475)
  line L9 (38.1525, 20.3475) -> (38.1525, 0)
  dimension "d188" = 1.9
  dimension "d189" = 0.717
  dimension "d190" = 7.6
  dimension "d191" = 2.4
  constraint coincident L0.end L3.start
  constraint perpendicular L0 L3
  constraint horizontal L5
  constraint vertical L6
  constraint horizontal L7
  constraint vertical L8
  measures "d188" distance of L0.end L3.end
  measures "d189" distance of L3.end L4.end
  measures "d190" distance of L4.end L5.end
  measures "d191" distance of L4.end L7.end
extrude "Extrude15" cut sketch "Sketch7" against normal through all contours L0 L5 L6 L8 | L0 L6 L7 L8
fillet "Fillet2" radius 0.25 12 edges at (74.15, 15.1865, 29.61) (74.15, 19.6865, 29.61) (74.15, 15.1865, 41.61) (74.15, 19.6865, 41.61) (72.7494, 18.4475, 49.6081) (73.9746, 20.8475, 49.7823) (72.9044, 20.8475, 57.3066) (71.6792, 18.4475, 57.1323) (67.9125, 14.4565, 26.36) (67.9125, 14.4565, 44.86) (67.9125, 20.3475, 44.86) (67.9125, 20.3475, 26.36)
sketch "Sketch8" plane through (0, 0, 0) normal (0, -1, 0) x (1, 0, 0)
  line L0 (-66.675, -57.15) -> (-66.675, 57.15)
  line L1 (-66.675, 57.15) -> (-4.8755, 57.15)
  line L2 (-4.8755, 57.15) -> (-1.4324, 83.6771)
  line L3 (-1.4324, 83.6771) -> (54.5604, 98.6803)
  line L4 (54.5604, 98.6803) -> (65.0234, 59.6321)
  line L5 (65.0234, 59.6321) -> (66.675, 48.0199)
  line L6 (66.675, -68.58) -> (28.575, -68.58)
  line L7 (28.575, -68.58) -> (28.575, -74.295)
  line L8 (28.575, -74.295) -> (9.525, -74.295)
  line L9 (9.525, -74.295) -> (9.525, -66.675)
  line L10 (9.525, -66.675) -> (-9.525, -66.675)
  line L11 (-9.525, -66.675) -> (-9.525, -57.15)
  line L12 (-9.525, -57.15) -> (-66.675, -57.15)
  line L13 (-22, -69.625) -> (-22, -79.15)
  line L14 (-22, -79.15) -> (-2.95, -79.15)
  line L15 (-2.95, -79.15) -> (-2.95, -86.77)
  line L16 (-2.95, -86.77) -> (41.05, -86.77)
  line L17 (41.05, -86.77) -> (41.05, -81.055)
  line L18 (41.05, -81.055) -> (79.15, -81.055)
  line L19 (79.15, -81.055) -> (79.15, 48.9026)
  line L20 (79.15, 48.9026) -> (77.2681, 62.1339)
  line L21 (77.2681, 62.1339) -> (63.3816, 113.959)
  line L22 (63.3816, 113.959) -> (-12.7285, 93.5653)
  line L23 (-12.7285, 93.5653) -> (-15.8359, 69.625)
  line L24 (-15.8359, 69.625) -> (-79.15, 69.625)
  line L25 (-79.15, 69.625) -> (-79.15, -69.625)
  line L26 (-79.15, -69.625) -> (-22, -69.625)
  circle A0 centre (-72.9628, -63.4378) radius 1.025
  circle A1 centre (-72.9628, 63.4378) radius 1.025
  circle A2 centre (72.9628, -74.8678) radius 1.025
  circle A3 centre (59.0066, 106.3813) radius 1.025
  line L27 (66.675, -68.58) -> (66.675, -58.58) construction
  line L28 (66.675, -58.58) -> (79.15, -58.58)
  line L29 (-66.675, -57.15) -> (-66.675, -47.15) construction
  line L30 (-66.675, -47.15) -> (-79.15, -47.15)
  line L31 (54.5604, 98.6803) -> (57.1486, 89.021) construction
  line L32 (57.1486, 89.021) -> (69.1985, 92.2498)
  line L33 (-66.675, 57.15) -> (-66.675, 47.15) construction
  line L34 (-66.675, 47.15) -> (-79.15, 47.15)
  line L35 (66.675, 48.0199) -> (66.675, -68.58)
  dimension "d197" = 10
  dimension "d198" = 10
  dimension "d199" = 10
  dimension "d200" = 10
  constraint coincident L6.start L27.start
  constraint perpendicular L6 L27
  constraint coincident L19 L28.end
  constraint perpendicular L19 L28
  constraint coincident L0.start L12.end
  constraint coincident L0 L29.end
  constraint coincident L25 L30.end
  constraint perpendicular L25 L30
  constraint coincident L3.end L4.start
  constraint coincident L4 L31.end
  constraint coincident L21 L32.end
  constraint perpendicular L21 L32
  constraint coincident L0.end L1.start
  constraint coincident L0 L33.end
  constraint coincident L25 L34.end
  constraint perpendicular L25 L34
  measures "d197" distance of L6.start L27.end
  measures "d198" distance of L0.start L29.end
  measures "d199" distance of L3.end L31.end
  measures "d200" distance of L0.end L33.end
draft "Draft1" angle -2.75 neutral plane through (79.15, 0, -81.055) pull (1, 0, 0) 1 faces at (-29.1288, 0, 61.3083)
extrude "Extrude16" cut sketch "Sketch8" against normal blind 11.8975 contours L0 L6 L7 L8 L9 L10 L11 L12 L13 L14 L15 L16 L17 L18 L19 L25 L26 L28 L30 L35 | L0 L1 L2 L3 L4 L21 L22 L23 L24 L25 L32 L34
sketch "Sketch9" plane through (0, 11.8975, 0) normal (0, -1, 0) x (1, 0, 0)
  circle A0 centre (-72.9628, -63.4378) radius 1.025
  circle A1 centre (72.9628, -74.8678) radius 1.025
  line L0 (66.675, -68.58) -> (28.575, -68.58)
  line L1 (28.575, -68.58) -> (28.575, -74.295)
  line L2 (28.575, -74.295) -> (9.525, -74.295)
  line L3 (9.525, -74.295) -> (9.525, -66.675)
  line L4 (9.525, -66.675) -> (-9.525, -66.675)
  line L5 (-9.525, -66.675) -> (-9.525, -57.15)
  line L6 (-9.525, -57.15) -> (-66.675, -57.15)
  line L7 (-66.675, -57.15) -> (-66.675, -47.15)
  line L8 (-66.675, -47.15) -> (-79.15, -47.15)
  line L9 (-79.15, -47.15) -> (-79.15, -69.625)
  line L10 (-79.15, -69.625) -> (-22, -69.625)
  line L11 (-22, -69.625) -> (-22, -79.15)
  line L12 (-22, -79.15) -> (-2.95, -79.15)
  line L13 (-2.95, -79.15) -> (-2.95, -86.77)
  line L14 (-2.95, -86.77) -> (41.05, -86.77)
  line L15 (41.05, -86.77) -> (41.05, -81.055)
  line L16 (41.05, -81.055) -> (79.15, -81.055)
  line L17 (79.15, -81.055) -> (79.15, -58.58)
  line L18 (79.15, -58.58) -> (66.675, -58.58)
  line L19 (-66.675, -57.15) -> (-56.675, -57.15) construction
  line L20 (-56.675, -57.15) -> (-56.675, -69.625) construction
  line L21 (19.05, -86.77) -> (19.05, -74.295) construction
  line L22 (-56.675, -63.3875) -> (-9.525, -63.3875) construction
  circle A2 centre (19.05, -80.5325) radius 1.275
  circle A3 centre (-33.1, -63.3875) radius 1.275
  line L23 (66.675, -58.58) -> (66.675, -68.58)
  dimension "d205" = 10
  dimension "d207" = 2.55
  dimension "d208" = 2.55
  constraint coincident L6.end L7.start
  constraint perpendicular L7 L19
  constraint coincident L10 L20.end
  constraint perpendicular L10 L20
  constraint midpoint L14 L21.start
  constraint midpoint L2 L21.end
  constraint midpoint L20 L22.start
  constraint coincident L5 L22.end
  constraint perpendicular L5 L22
  constraint midpoint L21 A2.centre
  constraint midpoint L22 A3.centre
  measures "d205" distance of L6.end L19.end
  measures "d207" diameter of A2
  measures "d208" diameter of A3